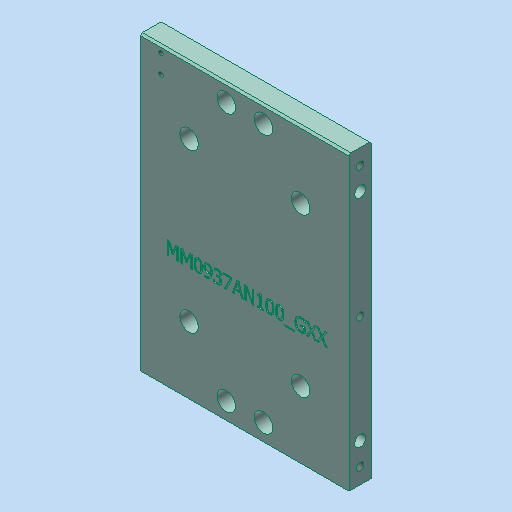
# Autodesk Inventor part: MM0937AN100_G01_102
Saved by Autodesk Inventor 2023.3 (Build 273359000, 359)
## iProperties
RuleStatus: InUse
Created: 2020-12-04
Part Number: MM0937AN100_G01_102
Material: 3.3547 AlMg4,5Mn0,7 - AW 5083
Description: =<RBPARTNOTITLE2>
Document SubType Name: Modeling
Designer: RUD
Mass: 543.712 g
Surface Area: 470.565 cm^2
Volume: 201.375 cm^3
Density: 2.7 g/cm^3
Appearance: Jade-H
AnP_Kategorie: 1
AnP_Material: =<Material>
AnP_TemplVers: 20200821
RBDOCUMENTTYPE: DRF
RBDOCUMENTVERSION: 00
RBDRAWINGMAINSCALE: 1:1
RBDRAWINGMISSINGSPEC: --
RBDRAWINGVOLUME: --
RBDSV1: 0850
RBGBEDGESIN1: +0,5
RBGBEDGESIN2: +0,2
RBGBEDGESOUT1: -0,3
RBGBEDGESOUT2: -0,1
RBMATERIAL: =<Material>
RBMATMEETS: --
RBMATNO: =<Part Number>
RBPARTMADEOF: Fl.120x12x160
RBPARTNO: SIEHE MNR
RBPARTNOTITLE1: manufactured part
RBPARTNOTITLE2: Anfertigungsteil
RBPARTSAFETYINDICATOR: --
RBSURFACE: anodised colourless
RBSURFACE2: eloxiert farblos
RBZEDGESNORM: ISO13715:2002-06
RBZGENDIMCLASS: m
RBZGENDIMNORM: ISO 2768-1:1989-11
RBZGENGEOCLASS: H
RBZGENGEONORM: ISO 2768-2:1989-11
RBZSURFACENORM: ISO13D2:2002-02
RBZTOLERANCENORM: ISO 14405-1:2010-12
Author: RUD
Keywords: =<RBPARTMADEOF>
Comments: =<RBSURFACE2>
Revision Number: 01
Autodesk Inventor part; units mm, degrees
ref_plane "YZ Plane" through (0, 0, 0) normal (1, 0, 0) x (0, 1, 0)
ref_plane "XZ Plane" through (0, 0, 0) normal (0, 1, 0) x (-1, 0, 0)
ref_plane "XY Plane" through (0, 0, 0) normal (0, 0, 1) x (1, 0, 0)
sketch "Skizze1" plane through (0, 0, 0) normal (0, 0, 1) x (1, 0, 0)
  line L0 (0, 109.9) -> (0, -109.9) projected
  line L1 (-78.4, 0) -> (78.4, 0) projected
  line L2 (-56, 78.5) -> (56, 78.5)
  line L3 (56, 78.5) -> (56, -78.5)
  line L4 (56, -78.5) -> (-56, -78.5)
  line L5 (-56, -78.5) -> (-56, 78.5)
  dimension "d0" = 112
  dimension "d1" = 157
  constraints: 8 end point, 2 parallel, 1 horizontal, 1 perpendicular, 2 other
  measures "d0" distance between parallel lines of L3 L5
  measures "d1" distance between parallel lines of L4 L2
extrude "Extrusion1" add sketch "Skizze1" along normal blind 12
sketch "Skizze2" plane through (0, 0, 12) normal (0, 0, 1) x (1, 0, 0)
  line L0 (0, 109.9) -> (0, -109.9) projected
  line L1 (-78.4, 0) -> (78.4, 0) projected
  point P0 (-30, 42.5)
  point P1 (-10, 69.5)
  point P2 (10, 69.5)
  point P3 (30, 42.5)
  point P4 (30, -42.5)
  point P5 (10, -69.5)
  point P6 (-10, -69.5)
  point P7 (-30, -42.5)
  dimension "d4" = 20
  dimension "d5" = 60
  dimension "d39" = 85
  dimension "d40" = 139
  constraints: 6 symmetric about line
  measures "d4" distance of point (-10, 69.5) point (10, 69.5)
  measures "d5" distance of point (30, 42.5) point (-30, 42.5)
  measures "d39" distance of point (-30, -42.5) point (-30, 42.5)
  measures "d40" distance of point (-10, -69.5) point (-10, 69.5)
hole "Bohrung1" at (-30, 42.5, 12) at (-10, 69.5, 12) at (10, 69.5, 12) at (30, 42.5, 12) at (30, -42.5, 12) at (10, -69.5, 12) at (-10, -69.5, 12) at (-30, -42.5, 12) direction (0, 0, -1) diameter 5.5 end through all counterbore diameter 10 counterbore depth 7
sketch "Skizze3" plane through (0, 0, 0) normal (0, 0, -1) x (-1, 0, 0)
  line L0 (0, -109.9) -> (0, 109.9) projected
  line L1 (-78.4, 0) -> (78.4, 0) projected
  point P0 (0, 40)
  point P1 (0, -40)
  dimension "d15" = 80
  constraints: 1 point on line, 1 symmetric about line
  measures "d15" distance of point (0, -40) point (0, 40)
hole "Bohrung2" at (0, 40, 0) at (0, -40, 0) direction (0, 0, 1) diameter 9 depth 2.1
sketch "Skizze4" plane through (-56, -78.5, 0) normal (-1, 0, 0) x (0, 0, 1)
  line L0 (0, 188.4) -> (0, -31.4) projected
  line L1 (-2.4, 78.5) -> (14.4, 78.5) projected
  line L2 (0, 157) -> (12, 157) projected
  point P0 (6, 78.5)
  point P1 (6, 148.5)
  point P2 (6, 8.5)
  point P3 (6, 157)
  dimension "d23" = 140
  constraints: 2 midpoint, 2 vertical alignment, 1 symmetric about line
  measures "d23" distance of point (6, 8.5) point (6, 148.5)
hole "Bohrung3" at (-56, 0, 6) at (-56, 70, 6) at (-56, -70, 6) direction (1, 0, 0) diameter 4.134 depth 18 tip angle 118 thread size "M5x0.8" designation "M5" class "6H" standard "ISO Metric profile"
sketch "Skizze5" plane through (-56, -78.5, 0) normal (-1, 0, 0) x (0, 0, 1)
  line L0 (-2.4, 78.5) -> (14.4, 78.5) projected
  circle A0 centre (6, 78.5) radius 2.067 projected
  point P0 (6, 136.5)
  point P1 (6, 20.5)
  dimension "d31" = 116
  constraints: 1 symmetric about line, 1 vertical alignment
  measures "d31" distance of point (6, 20.5) point (6, 136.5)
hole "Bohrung4" at (-56, 58, 6) at (-56, -58, 6) direction (1, 0, 0) diameter 6 depth 12 tip angle 118
sketch "Skizze6" plane through (0, 0, 12) normal (0, 0, 1) x (1, 0, 0)
  line L0 (56, 78.5) -> (-56, 78.5) projected
  line L1 (0, 109.9) -> (0, -109.9) projected
  line L2 (-45, 75) -> (-45, 65)
  dimension "d44" = 45
  dimension "d45" = 3.5
  dimension "d46" = 10
  constraints: 2 coincident, 2 end point, 1 vertical
  measures "d44" distance from line of L1 point (-45, 75)
  measures "d45" distance from line of point (-45, 75) L0
  measures "d46" distance of L2.start L2.end
hole "Bohrung5" at (-45, 75, 12) at (-45, 65, 12) direction (0, 0, -1) diameter 2.459 end through all thread size "M3x0.5" designation "M3" class "6H" standard "ISO Metric profile"
mirror "Spiegeln1" about plane through (0, 0, 0) normal (1, 0, 0) of "Bohrung3", "Bohrung4"
sketch "Skizze8" plane through (-56, -78.5, 0) normal (0, -1, 0) x (1, 0, 0)
  line L0 (112, 0) -> (112, 12) projected
  line L1 (89, 6) -> (75, 6)
  point P0 (112, 6)
  dimension "d59" = 23
  dimension "d60" = 14
  constraints: 2 coincident, 2 end point, 1 horizontal, 1 horizontal alignment, 1 midpoint
  measures "d59" distance from line of point (89, 6) L0
  measures "d60" distance of L1.start L1.end
hole "Bohrung6" at (33, -78.5, 6) at (19, -78.5, 6) direction (0, 1, 0) diameter 4.917 depth 20 tip angle 118 thread size "M6x1" designation "M6" class "6H" standard "ISO Metric profile"
chamfer "Fase1" distance 1 angle 45 2 edges at (0, 78.5, 12) (0, 78.5, 0)
chamfer "Fase2" distance 0.2 angle 45 2 edges at (0, 35.5, 0) (0, -44.5, 0)
sketch "Skizze7" plane through (0, 0, 12) normal (0, 0, 1) x (1, 0, 0)
  line L0 (-42.4788, -10.3396) -> (43, -10.3396) construction
  line L1 (43, -10.3396) -> (43, -18.5) construction
  line L2 (43, -18.5) -> (-42.4788, -18.5) construction
  line L3 (-42.4788, -18.5) -> (-42.4788, -10.3396) construction
  line L4 (-56, -78.5) -> (56, -78.5) projected
  line L5 (-35.7681, -17.4871) -> (-36.6984, -17.4871)
  line L6 (-36.6984, -17.4871) -> (-36.6984, -11.4571)
  line L7 (-36.6984, -11.4571) -> (-38.525, -15.5584)
  line L8 (-38.525, -15.5584) -> (-39.0922, -15.5584)
  line L9 (-39.0922, -15.5584) -> (-40.9018, -11.4571)
  line L10 (-40.9018, -11.4571) -> (-40.9018, -17.4871)
  line L11 (-40.9018, -17.4871) -> (-41.7697, -17.4871)
  line L12 (-41.7697, -17.4871) -> (-41.7697, -10.4871)
  line L13 (-41.7697, -10.4871) -> (-40.499, -10.4871)
  line L14 (-40.499, -10.4871) -> (-38.7519, -14.3842)
  line L15 (-38.7519, -14.3842) -> (-37.0614, -10.4871)
  line L16 (-37.0614, -10.4871) -> (-35.7681, -10.4871)
  line L17 (-35.7681, -10.4871) -> (-35.7681, -17.4871)
  line L18 (-28.3483, -17.4871) -> (-29.2786, -17.4871)
  line L19 (-29.2786, -17.4871) -> (-29.2786, -11.4571)
  line L20 (-29.2786, -11.4571) -> (-31.1052, -15.5584)
  line L21 (-31.1052, -15.5584) -> (-31.6725, -15.5584)
  line L22 (-31.6725, -15.5584) -> (-33.482, -11.4571)
  line L23 (-33.482, -11.4571) -> (-33.482, -17.4871)
  line L24 (-33.482, -17.4871) -> (-34.3499, -17.4871)
  line L25 (-34.3499, -17.4871) -> (-34.3499, -10.4871)
  line L26 (-34.3499, -10.4871) -> (-33.0793, -10.4871)
  line L27 (-33.0793, -10.4871) -> (-31.3321, -14.3842)
  line L28 (-31.3321, -14.3842) -> (-29.6417, -10.4871)
  line L29 (-29.6417, -10.4871) -> (-28.3483, -10.4871)
  line L30 (-28.3483, -10.4871) -> (-28.3483, -17.4871)
  spline S0 degree 2 poles (-22.7721, -13.9871) (-22.7721, -15.8704) (-23.8669, -17.6346) (-25.0071, -17.6346) knots 0 0 0 1 2 2 2
  spline S1 degree 2 poles (-25.0071, -17.6346) (-26.1644, -17.6346) (-27.2478, -15.8364) (-27.2478, -13.9928) knots 0 0 0 1 2 2 2
  spline S2 degree 2 poles (-27.2478, -13.9928) (-27.2478, -12.0981) (-26.153, -10.3453) (-25.0071, -10.3453) knots 0 0 0 1 2 2 2
  spline S3 degree 2 poles (-25.0071, -10.3453) (-23.8556, -10.3453) (-22.7721, -12.1605) (-22.7721, -13.9871) knots 0 0 0 1 2 2 2
  spline S4 degree 2 poles (-23.9747, -16.12) (-23.8386, -15.774) (-23.7251, -14.7075) (-23.7251, -13.9871) knots 0 0 0 1 2 2 2
  spline S5 degree 2 poles (-23.7251, -13.9871) (-23.7251, -13.2667) (-23.8386, -12.2059) (-23.9804, -11.8485) knots 0 0 0 1 2 2 2
  spline S6 degree 2 poles (-23.9804, -11.8485) (-24.1222, -11.4912) (-24.6157, -11.1225) (-25.0071, -11.1225) knots 0 0 0 1 2 2 2
  spline S7 degree 2 poles (-25.0071, -11.1225) (-25.3986, -11.1225) (-25.9034, -11.4912) (-26.0509, -11.8599) knots 0 0 0 1 2 2 2
  spline S8 degree 2 poles (-26.0509, -11.8599) (-26.1927, -12.2173) (-26.2948, -13.3064) (-26.2948, -13.9928) knots 0 0 0 1 2 2 2
  spline S9 degree 2 poles (-26.2948, -13.9928) (-26.2948, -14.7302) (-26.2041, -15.7173) (-26.0566, -16.103) knots 0 0 0 1 2 2 2
  spline S10 degree 2 poles (-26.0566, -16.103) (-25.9204, -16.4661) (-25.4156, -16.8575) (-25.0071, -16.8575) knots 0 0 0 1 2 2 2
  spline S11 degree 2 poles (-25.0071, -16.8575) (-24.6214, -16.8575) (-24.1165, -16.4887) (-23.9747, -16.12) knots 0 0 0 1 2 2 2
  spline S12 degree 2 poles (-22.0687, -12.7618) (-22.0687, -12.2229) (-21.717, -11.3267) (-21.4107, -11.0033) knots 0 0 0 1 2 2 2
  spline S13 degree 2 poles (-21.4107, -11.0033) (-21.1214, -10.6913) (-20.2762, -10.3453) (-19.8451, -10.3453) knots 0 0 0 1 2 2 2
  spline S14 degree 2 poles (-19.8451, -10.3453) (-19.3629, -10.3453) (-18.5801, -10.6686) (-18.2908, -10.975) knots 0 0 0 1 2 2 2
  spline S15 degree 2 poles (-18.2908, -10.975) (-17.9277, -11.3607) (-17.5306, -12.6087) (-17.5306, -13.5673) knots 0 0 0 1 2 2 2
  spline S16 degree 2 poles (-17.5306, -13.5673) (-17.5306, -14.4353) (-17.9221, -15.9896) (-18.3021, -16.5058) knots 0 0 0 1 2 2 2
  spline S17 degree 2 poles (-18.3021, -16.5058) (-18.7049, -17.0503) (-19.8394, -17.6233) (-20.6676, -17.6233) knots 0 0 0 1 2 2 2
  spline S18 degree 2 poles (-20.6676, -17.6233) (-20.8548, -17.6233) (-21.2802, -17.5836) (-21.4618, -17.5268) knots 0 0 0 1 2 2 2
  line L31 (-21.4618, -17.5268) -> (-21.4618, -16.6249)
  line L32 (-21.4618, -16.6249) -> (-21.4164, -16.6249)
  spline S19 degree 2 poles (-21.4164, -16.6249) (-21.2973, -16.693) (-20.7981, -16.8121) (-20.5428, -16.8121) knots 0 0 0 1 2 2 2
  spline S20 degree 2 poles (-20.5428, -16.8121) (-19.6238, -16.8121) (-18.5744, -15.5981) (-18.5007, -14.475) knots 0 0 0 1 2 2 2
  spline S21 degree 2 poles (-18.5007, -14.475) (-18.875, -14.7302) (-19.5558, -14.9628) (-19.9585, -14.9628) knots 0 0 0 1 2 2 2
  spline S22 degree 2 poles (-19.9585, -14.9628) (-20.3443, -14.9628) (-20.9853, -14.7926) (-21.3086, -14.5487) knots 0 0 0 1 2 2 2
  spline S23 degree 2 poles (-21.3086, -14.5487) (-21.683, -14.2594) (-22.0687, -13.3802) (-22.0687, -12.7618) knots 0 0 0 1 2 2 2
  spline S24 degree 2 poles (-18.478, -13.3575) (-18.478, -12.6484) (-18.7389, -11.7521) (-18.9715, -11.5082) knots 0 0 0 1 2 2 2
  spline S25 degree 2 poles (-18.9715, -11.5082) (-19.1757, -11.2813) (-19.6011, -11.1111) (-19.8507, -11.1111) knots 0 0 0 1 2 2 2
  spline S26 degree 2 poles (-19.8507, -11.1111) (-20.4293, -11.1111) (-21.1157, -11.9393) (-21.1157, -12.7221) knots 0 0 0 1 2 2 2
  spline S27 degree 2 poles (-21.1157, -12.7221) (-21.1157, -13.1646) (-20.8888, -13.7375) (-20.6392, -13.9417) knots 0 0 0 1 2 2 2
  spline S28 degree 2 poles (-20.6392, -13.9417) (-20.4577, -14.0892) (-20.0096, -14.1857) (-19.7486, -14.1857) knots 0 0 0 1 2 2 2
  spline S29 degree 2 poles (-19.7486, -14.1857) (-19.448, -14.1857) (-18.7559, -13.9758) (-18.495, -13.7999) knots 0 0 0 1 2 2 2
  spline S30 degree 2 poles (-18.495, -13.7999) (-18.4893, -13.7319) (-18.478, -13.4993) (-18.478, -13.3575) knots 0 0 0 1 2 2 2
  spline S31 degree 2 poles (-14.734, -11.1508) (-14.9893, -11.1508) (-15.4942, -11.2756) (-15.7381, -11.372) knots 0 0 0 1 2 2 2
  spline S32 degree 2 poles (-15.7381, -11.372) (-15.965, -11.4685) (-16.2997, -11.6727) (-16.4302, -11.7635) knots 0 0 0 1 2 2 2
  line L33 (-16.4302, -11.7635) -> (-16.4869, -11.7635)
  line L34 (-16.4869, -11.7635) -> (-16.4869, -10.7708)
  spline S33 degree 2 poles (-16.4869, -10.7708) (-16.1806, -10.6062) (-15.1311, -10.3396) (-14.6603, -10.3396) knots 0 0 0 1 2 2 2
  spline S34 degree 2 poles (-14.6603, -10.3396) (-14.1838, -10.3396) (-13.4747, -10.5325) (-13.1854, -10.7367) knots 0 0 0 1 2 2 2
  spline S35 degree 2 poles (-13.1854, -10.7367) (-12.8791, -10.9579) (-12.5614, -11.599) (-12.5614, -12.0301) knots 0 0 0 1 2 2 2
  spline S36 degree 2 poles (-12.5614, -12.0301) (-12.5614, -12.6087) (-13.3216, -13.4823) (-13.8548, -13.5957) knots 0 0 0 1 2 2 2
  line L35 (-13.8548, -13.5957) -> (-13.8548, -13.6638)
  spline S37 degree 2 poles (-13.8548, -13.6638) (-13.6336, -13.7092) (-13.1287, -13.9134) (-12.9131, -14.1176) knots 0 0 0 1 2 2 2
  spline S38 degree 2 poles (-12.9131, -14.1176) (-12.6976, -14.3161) (-12.4253, -14.9515) (-12.4253, -15.4109) knots 0 0 0 1 2 2 2
  spline S39 degree 2 poles (-12.4253, -15.4109) (-12.4253, -15.8818) (-12.7486, -16.6816) (-13.0436, -16.9879) knots 0 0 0 1 2 2 2
  spline S40 degree 2 poles (-13.0436, -16.9879) (-13.3499, -17.3056) (-14.2178, -17.6346) (-14.7681, -17.6346) knots 0 0 0 1 2 2 2
  spline S41 degree 2 poles (-14.7681, -17.6346) (-15.2956, -17.6346) (-16.328, -17.3793) (-16.6797, -17.2035) knots 0 0 0 1 2 2 2
  line L36 (-16.6797, -17.2035) -> (-16.6797, -16.2108)
  line L37 (-16.6797, -16.2108) -> (-16.6117, -16.2108)
  spline S42 degree 2 poles (-16.6117, -16.2108) (-16.3167, -16.4263) (-15.3183, -16.8234) (-14.8248, -16.8234) knots 0 0 0 1 2 2 2
  spline S43 degree 2 poles (-14.8248, -16.8234) (-14.5355, -16.8234) (-13.9569, -16.6419) (-13.764, -16.432) knots 0 0 0 1 2 2 2
  spline S44 degree 2 poles (-13.764, -16.432) (-13.5768, -16.2221) (-13.3783, -15.7229) (-13.3783, -15.3429) knots 0 0 0 1 2 2 2
  spline S45 degree 2 poles (-13.3783, -15.3429) (-13.3783, -14.9628) (-13.5995, -14.4693) (-13.7981, -14.3275) knots 0 0 0 1 2 2 2
  spline S46 degree 2 poles (-13.7981, -14.3275) (-13.9966, -14.1857) (-14.5355, -14.0779) (-14.8532, -14.0779) knots 0 0 0 1 2 2 2
  line L38 (-14.8532, -14.0779) -> (-15.2503, -14.0779)
  line L39 (-15.2503, -14.0779) -> (-15.2503, -13.3007)
  line L40 (-15.2503, -13.3007) -> (-14.9383, -13.3007)
  spline S47 degree 2 poles (-14.9383, -13.3007) (-14.3086, -13.3007) (-13.5144, -12.6994) (-13.5144, -12.1265) knots 0 0 0 1 2 2 2
  spline S48 degree 2 poles (-13.5144, -12.1265) (-13.5144, -11.8599) (-13.7186, -11.4798) (-13.8832, -11.3664) knots 0 0 0 1 2 2 2
  spline S49 degree 2 poles (-13.8832, -11.3664) (-14.059, -11.2473) (-14.4901, -11.1508) (-14.734, -11.1508) knots 0 0 0 1 2 2 2
  line L41 (-6.9739, -11.5366) -> (-10.0031, -17.4871)
  line L42 (-10.0031, -17.4871) -> (-11.0015, -17.4871)
  line L43 (-11.0015, -17.4871) -> (-7.8021, -11.3096)
  line L44 (-7.8021, -11.3096) -> (-11.4156, -11.3096)
  line L45 (-11.4156, -11.3096) -> (-11.4156, -10.4871)
  line L46 (-11.4156, -10.4871) -> (-6.9739, -10.4871)
  line L47 (-6.9739, -10.4871) -> (-6.9739, -11.5366)
  line L48 (-6.6733, -17.4871) -> (-4.3135, -10.4871)
  line L49 (-4.3135, -10.4871) -> (-3.1676, -10.4871)
  line L50 (-3.1676, -10.4871) -> (-0.8078, -17.4871)
  line L51 (-0.8078, -17.4871) -> (-1.7892, -17.4871)
  line L52 (-1.7892, -17.4871) -> (-2.4245, -15.5301)
  line L53 (-2.4245, -15.5301) -> (-5.0963, -15.5301)
  line L54 (-5.0963, -15.5301) -> (-5.7316, -17.4871)
  line L55 (-5.7316, -17.4871) -> (-6.6733, -17.4871)
  line L56 (-2.6797, -14.7359) -> (-3.7632, -11.4401)
  line L57 (-3.7632, -11.4401) -> (-4.841, -14.7359)
  line L58 (-4.841, -14.7359) -> (-2.6797, -14.7359)
  line L59 (4.8648, -17.4871) -> (3.8211, -17.4871)
  line L60 (3.8211, -17.4871) -> (0.7238, -11.4515)
  line L61 (0.7238, -11.4515) -> (0.7238, -17.4871)
  line L62 (0.7238, -17.4871) -> (-0.1441, -17.4871)
  line L63 (-0.1441, -17.4871) -> (-0.1441, -10.4871)
  line L64 (-0.1441, -10.4871) -> (1.1776, -10.4871)
  line L65 (1.1776, -10.4871) -> (3.9969, -16.0293)
  line L66 (3.9969, -16.0293) -> (3.9969, -10.4871)
  line L67 (3.9969, -10.4871) -> (4.8648, -10.4871)
  line L68 (4.8648, -10.4871) -> (4.8648, -17.4871)
  line L69 (10.0496, -17.4871) -> (6.6347, -17.4871)
  line L70 (6.6347, -17.4871) -> (6.6347, -16.7724)
  line L71 (6.6347, -16.7724) -> (7.9053, -16.7724)
  line L72 (7.9053, -16.7724) -> (7.9053, -12.0811)
  line L73 (7.9053, -12.0811) -> (6.6347, -12.0811)
  line L74 (6.6347, -12.0811) -> (6.6347, -11.4401)
  spline S50 degree 2 poles (6.6347, -11.4401) (7.3551, -11.4401) (8.0358, -11.0317) (8.0812, -10.4644) knots 0 0 0 1 2 2 2
  line L75 (8.0812, -10.4644) -> (8.8073, -10.4644)
  line L76 (8.8073, -10.4644) -> (8.8073, -16.7724)
  line L77 (8.8073, -16.7724) -> (10.0496, -16.7724)
  line L78 (10.0496, -16.7724) -> (10.0496, -17.4871)
  spline S51 degree 2 poles (15.6938, -13.9871) (15.6938, -15.8704) (14.599, -17.6346) (13.4588, -17.6346) knots 0 0 0 1 2 2 2
  spline S52 degree 2 poles (13.4588, -17.6346) (12.3016, -17.6346) (11.2181, -15.8364) (11.2181, -13.9928) knots 0 0 0 1 2 2 2
  spline S53 degree 2 poles (11.2181, -13.9928) (11.2181, -12.0981) (12.313, -10.3453) (13.4588, -10.3453) knots 0 0 0 1 2 2 2
  spline S54 degree 2 poles (13.4588, -10.3453) (14.6104, -10.3453) (15.6938, -12.1605) (15.6938, -13.9871) knots 0 0 0 1 2 2 2
  spline S55 degree 2 poles (14.4912, -16.12) (14.6274, -15.774) (14.7408, -14.7075) (14.7408, -13.9871) knots 0 0 0 1 2 2 2
  spline S56 degree 2 poles (14.7408, -13.9871) (14.7408, -13.2667) (14.6274, -12.2059) (14.4856, -11.8485) knots 0 0 0 1 2 2 2
  spline S57 degree 2 poles (14.4856, -11.8485) (14.3438, -11.4912) (13.8502, -11.1225) (13.4588, -11.1225) knots 0 0 0 1 2 2 2
  spline S58 degree 2 poles (13.4588, -11.1225) (13.0674, -11.1225) (12.5626, -11.4912) (12.4151, -11.8599) knots 0 0 0 1 2 2 2
  spline S59 degree 2 poles (12.4151, -11.8599) (12.2732, -12.2173) (12.1711, -13.3064) (12.1711, -13.9928) knots 0 0 0 1 2 2 2
  spline S60 degree 2 poles (12.1711, -13.9928) (12.1711, -14.7302) (12.2619, -15.7173) (12.4094, -16.103) knots 0 0 0 1 2 2 2
  spline S61 degree 2 poles (12.4094, -16.103) (12.5455, -16.4661) (13.0504, -16.8575) (13.4588, -16.8575) knots 0 0 0 1 2 2 2
  spline S62 degree 2 poles (13.4588, -16.8575) (13.8446, -16.8575) (14.3494, -16.4887) (14.4912, -16.12) knots 0 0 0 1 2 2 2
  spline S63 degree 2 poles (20.9467, -13.9871) (20.9467, -15.8704) (19.8519, -17.6346) (18.7117, -17.6346) knots 0 0 0 1 2 2 2
  spline S64 degree 2 poles (18.7117, -17.6346) (17.5544, -17.6346) (16.471, -15.8364) (16.471, -13.9928) knots 0 0 0 1 2 2 2
  spline S65 degree 2 poles (16.471, -13.9928) (16.471, -12.0981) (17.5658, -10.3453) (18.7117, -10.3453) knots 0 0 0 1 2 2 2
  spline S66 degree 2 poles (18.7117, -10.3453) (19.8632, -10.3453) (20.9467, -12.1605) (20.9467, -13.9871) knots 0 0 0 1 2 2 2
  spline S67 degree 2 poles (19.7441, -16.12) (19.8802, -15.774) (19.9937, -14.7075) (19.9937, -13.9871) knots 0 0 0 1 2 2 2
  spline S68 degree 2 poles (19.9937, -13.9871) (19.9937, -13.2667) (19.8802, -12.2059) (19.7384, -11.8485) knots 0 0 0 1 2 2 2
  spline S69 degree 2 poles (19.7384, -11.8485) (19.5966, -11.4912) (19.1031, -11.1225) (18.7117, -11.1225) knots 0 0 0 1 2 2 2
  spline S70 degree 2 poles (18.7117, -11.1225) (18.3202, -11.1225) (17.8154, -11.4912) (17.6679, -11.8599) knots 0 0 0 1 2 2 2
  spline S71 degree 2 poles (17.6679, -11.8599) (17.5261, -12.2173) (17.424, -13.3064) (17.424, -13.9928) knots 0 0 0 1 2 2 2
  spline S72 degree 2 poles (17.424, -13.9928) (17.424, -14.7302) (17.5147, -15.7173) (17.6622, -16.103) knots 0 0 0 1 2 2 2
  spline S73 degree 2 poles (17.6622, -16.103) (17.7984, -16.4661) (18.3032, -16.8575) (18.7117, -16.8575) knots 0 0 0 1 2 2 2
  spline S74 degree 2 poles (18.7117, -16.8575) (19.0974, -16.8575) (19.6023, -16.4887) (19.7441, -16.12) knots 0 0 0 1 2 2 2
  line L79 (26.659, -18.8939) -> (21.2587, -18.8939)
  line L80 (21.2587, -18.8939) -> (21.2587, -18.287)
  line L81 (21.2587, -18.287) -> (26.659, -18.287)
  line L82 (26.659, -18.287) -> (26.659, -18.8939)
  spline S75 degree 2 poles (30.2271, -17.6233) (29.4839, -17.6233) (28.253, -17.1695) (27.8105, -16.71) knots 0 0 0 1 2 2 2
  spline S76 degree 2 poles (27.8105, -16.71) (27.3681, -16.2448) (26.8972, -14.872) (26.8972, -13.9814) knots 0 0 0 1 2 2 2
  spline S77 degree 2 poles (26.8972, -13.9814) (26.8972, -13.1362) (27.3737, -11.7975) (27.8162, -11.321) knots 0 0 0 1 2 2 2
  spline S78 degree 2 poles (27.8162, -11.321) (28.2416, -10.8615) (29.4896, -10.3623) (30.2327, -10.3623) knots 0 0 0 1 2 2 2
  spline S79 degree 2 poles (30.2327, -10.3623) (30.5901, -10.3623) (31.2368, -10.4644) (31.5318, -10.5552) knots 0 0 0 1 2 2 2
  spline S80 degree 2 poles (31.5318, -10.5552) (31.77, -10.6233) (32.3486, -10.8729) (32.5245, -10.9636) knots 0 0 0 1 2 2 2
  line L83 (32.5245, -10.9636) -> (32.5245, -12.0868)
  line L84 (32.5245, -12.0868) -> (32.445, -12.0868)
  spline S81 degree 2 poles (32.445, -12.0868) (32.2692, -11.9336) (31.9005, -11.6557) (31.5601, -11.4968) knots 0 0 0 1 2 2 2
  spline S82 degree 2 poles (31.5601, -11.4968) (31.2765, -11.355) (30.5447, -11.1678) (30.1249, -11.1678) knots 0 0 0 1 2 2 2
  spline S83 degree 2 poles (30.1249, -11.1678) (29.1152, -11.1678) (27.8673, -12.6881) (27.8673, -13.9531) knots 0 0 0 1 2 2 2
  spline S84 degree 2 poles (27.8673, -13.9531) (27.8673, -14.6565) (28.1963, -15.7116) (28.5083, -16.0746) knots 0 0 0 1 2 2 2
  spline S85 degree 2 poles (28.5083, -16.0746) (28.8089, -16.4377) (29.6598, -16.8178) (30.193, -16.8178) knots 0 0 0 1 2 2 2
  spline S86 degree 2 poles (30.193, -16.8178) (30.5844, -16.8178) (31.3673, -16.7043) (31.6339, -16.5908) knots 0 0 0 1 2 2 2
  line L85 (31.6339, -16.5908) -> (31.6339, -14.7813)
  line L86 (31.6339, -14.7813) -> (30.0115, -14.7813)
  line L87 (30.0115, -14.7813) -> (30.0115, -13.9644)
  line L88 (30.0115, -13.9644) -> (32.5528, -13.9644)
  line L89 (32.5528, -13.9644) -> (32.5528, -17.022)
  spline S87 degree 2 poles (32.5528, -17.022) (32.377, -17.1014) (31.7757, -17.3453) (31.5204, -17.419) knots 0 0 0 1 2 2 2
  spline S88 degree 2 poles (31.5204, -17.419) (31.1744, -17.5212) (30.6185, -17.6233) (30.2271, -17.6233) knots 0 0 0 1 2 2 2
  line L90 (38.5601, -17.4871) -> (37.4937, -17.4871)
  line L91 (37.4937, -17.4871) -> (35.7919, -14.6962)
  line L92 (35.7919, -14.6962) -> (34.0561, -17.4871)
  line L93 (34.0561, -17.4871) -> (33.052, -17.4871)
  line L94 (33.052, -17.4871) -> (35.2814, -13.9814)
  line L95 (35.2814, -13.9814) -> (33.1201, -10.4871)
  line L96 (33.1201, -10.4871) -> (34.1865, -10.4871)
  line L97 (34.1865, -10.4871) -> (35.8543, -13.227)
  line L98 (35.8543, -13.227) -> (37.5561, -10.4871)
  line L99 (37.5561, -10.4871) -> (38.5601, -10.4871)
  line L100 (38.5601, -10.4871) -> (36.3705, -13.9361)
  line L101 (36.3705, -13.9361) -> (38.5601, -17.4871)
  line L102 (44.1476, -17.4871) -> (43.0812, -17.4871)
  line L103 (43.0812, -17.4871) -> (41.3794, -14.6962)
  line L104 (41.3794, -14.6962) -> (39.6436, -17.4871)
  line L105 (39.6436, -17.4871) -> (38.6395, -17.4871)
  line L106 (38.6395, -17.4871) -> (40.8689, -13.9814)
  line L107 (40.8689, -13.9814) -> (38.7076, -10.4871)
  line L108 (38.7076, -10.4871) -> (39.7741, -10.4871)
  line L109 (39.7741, -10.4871) -> (41.4418, -13.227)
  line L110 (41.4418, -13.227) -> (43.1436, -10.4871)
  line L111 (43.1436, -10.4871) -> (44.1476, -10.4871)
  line L112 (44.1476, -10.4871) -> (41.958, -13.9361)
  line L113 (41.958, -13.9361) -> (44.1476, -17.4871)
  dimension "d68" = 8.1604
  dimension "d69" = 85.4788
  dimension "d70" = 60
  constraints: 2 other
  measures "d68" distance of L2.end L0.start
  measures "d69" distance of L0.start L0.end
  measures "d70" distance between parallel lines of L4 L2
emboss "Prägen1" sketch "Skizze7" operation cut depth 0.5 direction (0, 0, -1)
